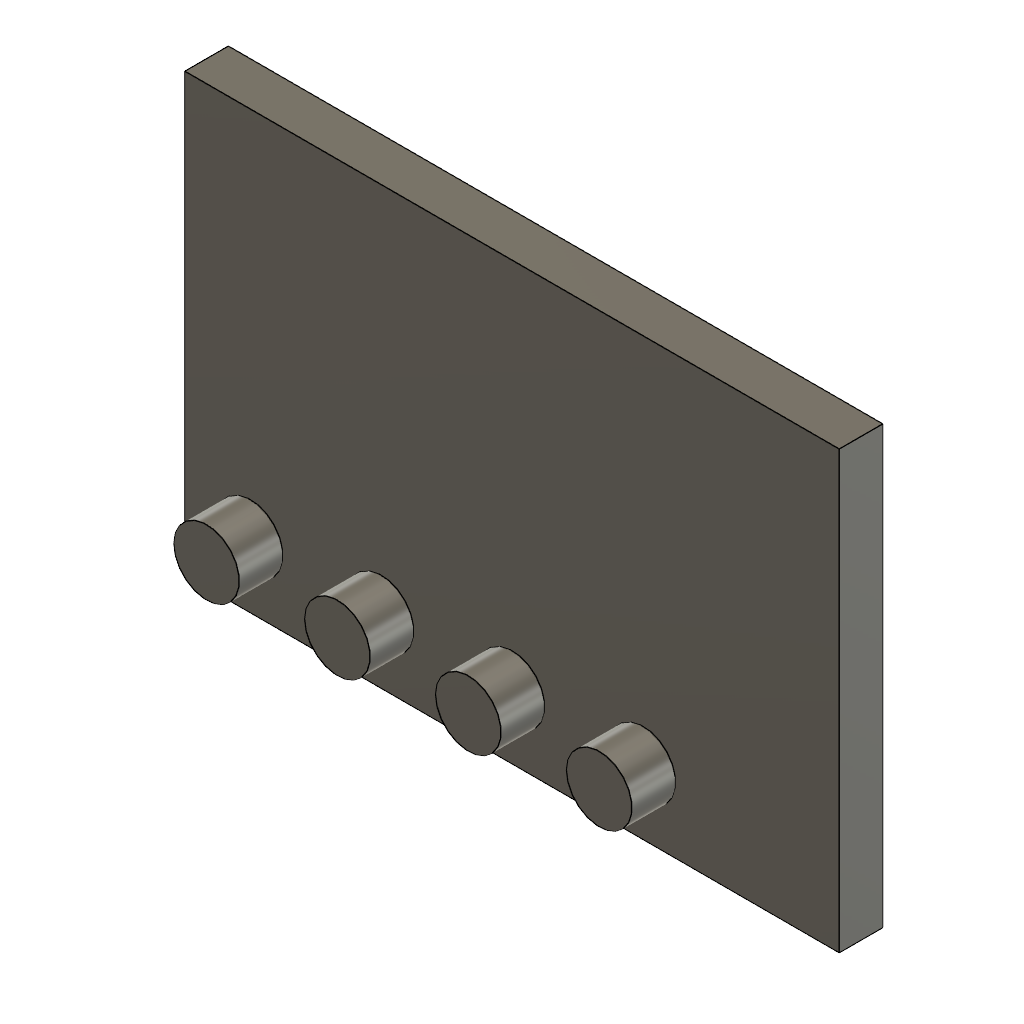
pat_rect_one_dir_extent (Autodesk Fusion 360 design; units mm, degrees)
part number: 2026-11-13-14-45-06-410
Autodesk Fusion 360 part; units mm, degrees
sketch "Sketch1" plane through (0, 0, 0) normal (0, 0, 1) x (1, 0, 0)
  line L0 (0, 0) -> (60, 0)
  line L1 (60, 0) -> (60, 40)
  line L2 (60, 40) -> (0, 40)
  line L3 (0, 40) -> (0, 0)
extrude "Extrude1" add sketch "Sketch1" along normal blind 4
sketch "Sketch2" plane through (0, 0, 4) normal (0, 0, 1) x (1, 0, 0)
  line L0 (0, 40) -> (0, 0)
  line L1 (0, 0) -> (60, 0)
  line L2 (60, 0) -> (60, 40)
  line L3 (60, 40) -> (0, 40)
  circle A0 centre (6, 6) radius 3
extrude "Extrude2" add sketch "Sketch2" along normal blind 4 contours A0
pattern_linear "R-Pattern1" count 4 spacing 12 along (1, 0, 0) count 3 spacing 0 along (1, 0, 0) of "Extrude2"
